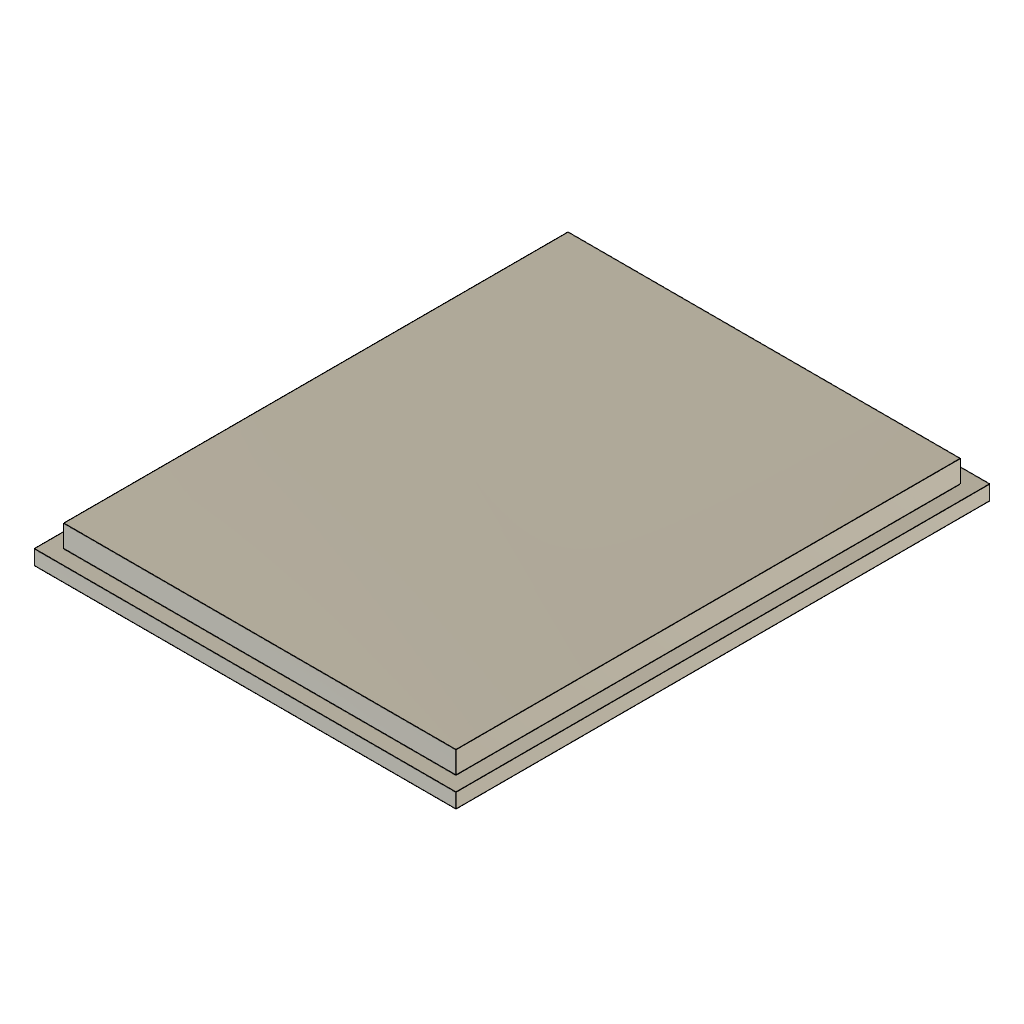
StatusDial_lidV1 (Autodesk Fusion 360 design; units mm, degrees)
part number: 2026-11-27-09-46-09-304
Autodesk Fusion 360 part; units mm, degrees
sketch "Sketch1" plane through (0, 0, 0) normal (0, 0, 1) x (1, 0, 0)
  line L0 (-48.1128, 32.4941) -> (9.2272, 32.4941)
  line L1 (9.2272, 32.4941) -> (9.2272, -40.0859)
  line L2 (9.2272, -40.0859) -> (-48.1128, -40.0859)
  line L3 (-48.1128, -40.0859) -> (-48.1128, 32.4941)
  dimension "d1" = 57.34
  dimension "d2" = 72.58
  constraint horizontal L0
  constraint vertical L1
  constraint horizontal L2
  constraint vertical L3
  measures "d1" distance of L0.start L0.end
  measures "d2" distance of L0.start L2.end
extrude "Extrude1" add sketch "Sketch1" along normal blind 2
sketch "Sketch2" plane through (0, 0, 2) normal (0, 0, 1) x (-1, 0, 0)
  line L0 (48.1128, 40.0859) -> (-9.2272, 40.0859)
  line L1 (-9.2272, 40.0859) -> (-9.2272, -32.4941)
  line L2 (-9.2272, -32.4941) -> (48.1128, -32.4941)
  line L3 (48.1128, -32.4941) -> (48.1128, 40.0859)
  line L4 (46.1128, -32.4941) -> (46.1128, -30.4941)
  line L5 (46.1128, 40.0859) -> (46.1128, 38.0859)
  line L6 (-7.2272, 40.0859) -> (-7.2272, 38.0859)
  line L7 (-7.2272, -32.4941) -> (-7.2272, -30.4941)
  line L8 (46.1128, -30.4941) -> (-7.2272, -30.4941)
  line L9 (-7.2272, -30.4941) -> (-7.2272, 38.0859)
  line L10 (-7.2272, 38.0859) -> (46.1128, 38.0859)
  line L11 (46.1128, 38.0859) -> (46.1128, -30.4941)
  dimension "d5" = 2
  dimension "d6" = 2
  dimension "d7" = 2
  dimension "d8" = 2
  dimension "d9" = 2
  dimension "d10" = 2
  dimension "d11" = 2
  dimension "d12" = 2
  constraint coincident L2 L4.start
  constraint perpendicular L2 L4
  constraint coincident L0 L5.start
  constraint perpendicular L0 L5
  constraint coincident L0 L6.start
  constraint perpendicular L0 L6
  constraint coincident L2 L7.start
  constraint perpendicular L2 L7
  measures "d5" distance of L4.start L4.end
  measures "d6" distance of L3 L4
  measures "d7" distance of L5.start L5.end
  measures "d8" distance of L3 L5
  measures "d9" distance of L6.start L6.end
  measures "d10" distance of L1 L6
  measures "d11" distance of L7.start L7.end
  measures "d12" distance of L1 L7
extrude "Extrude2" add sketch "Sketch2" along normal blind 3 contours L8 L9 L10 L11
